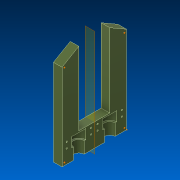
# Autodesk Inventor part: Floating Bed
Saved by Autodesk Inventor 2019 (Build 230136000, 136)
## iProperties
Created: 2019-03-21
Part Number: Floating Bed
Material: Generic
Document SubType Name: Modeling
Designer: Dell
Density: 1 g/cm^3
Appearance: Dark Olive
Mass: 1279.76 g
Surface Area: 1497.37 cm^2
Volume: 1279.76 cm^3
Author: Dell
Autodesk Inventor part; units mm, degrees
ref_plane "YZ Plane" through (0, 0, 0) normal (1, 0, 0) x (0, 1, 0)
ref_plane "XZ Plane" through (0, 0, 0) normal (0, 1, 0) x (-1, 0, 0)
ref_plane "XY Plane" through (0, 0, 0) normal (0, 0, 1) x (1, 0, 0)
sketch "Sketch1" plane through (0, 0, 0) normal (1, 0, 0) x (0, 1, 0)
  line L0 (80, 58.9167) -> (338.775, 58.9167)
  line L1 (80, 167.0833) -> (80, 58.9167)
  line L2 (336.4656, 167.0833) -> (80, 167.0833)
  line L3 (302.45, 226) -> (336.4656, 167.0833)
  line L4 (0, 226) -> (302.45, 226)
  line L5 (0, 226) -> (0, 0)
  line L6 (304.7594, 0) -> (0, 0)
  line L7 (304.7594, 0) -> (338.775, 58.9167)
  point P0 (0, 113)
  constraints: 16 end point
extrude "Extrusion1" add sketch "Sketch1" along normal blind 30
sketch "Sketch6" plane through (30, 0, 0) normal (1, 0, 0) x (0, 0, -1)
  circle A0 centre (-217.9704, 297.7535) radius 1.5 projected
  circle A1 centre (-218.1266, 9.9435) radius 1.5 projected
  circle A2 centre (-7.9983, 9.9012) radius 1.5 projected
  circle A3 centre (-7.8606, 297.8416) radius 1.5 projected
  point P0 (0, 0)
sketch "Sketch7" plane through (30, 0, 0) normal (1, 0, 0) x (0, 0, -1)
  point P0 (0, 0)
  point P1 (-7.8989, 9.8938)
  point P2 (-218.0482, 10.1478)
  point P3 (-218.2874, 297.6442)
  point P4 (-8.5245, 297.8695)
hole "Hole1" at (30, 9.8938, 7.8989) at (30, 10.1478, 218.0482) at (30, 297.6442, 218.2874) at (30, 297.8695, 8.5245) direction (-1, 0, 0) diameter 3 depth 10 tip angle 118
ref_plane "Work Plane1" through (0, 0, 113) normal (0, 0, 1) x (1, 0, 0)
sketch "Sketch12" plane through (30, 0, 0) normal (1, 0, 0) x (0, 0, -1)
  circle A0 centre (-218.2874, 297.6442) radius 1.5 projected
  circle A1 centre (-7.8989, 9.8938) radius 1.5 projected
  circle A2 centre (-218.0482, 10.1478) radius 1.5 projected
  circle A3 centre (-8.5245, 297.8695) radius 1.5 projected
  line L0 (-58.9167, 338.775) -> (-58.9167, 80) projected
  line L1 (-58.9167, 80) -> (-167.0833, 80) projected
  line L2 (-167.0833, 80) -> (-167.0833, 336.4656) projected
  line L3 (-167.0833, 336.4656) -> (-226, 302.45) projected
  line L4 (-226, 302.45) -> (-226, 0) projected
  line L5 (-226, 0) -> (0, 0) projected
  line L6 (0, 0) -> (0, 304.7594) projected
  line L7 (0, 304.7594) -> (-58.9167, 338.775) projected
  line L8 (-167.0833, 0) -> (-167.0833, 75)
  line L9 (-167.0833, 75) -> (-191.5833, 75)
  line L10 (-191.5833, 75) -> (-191.5833, 41)
  line L11 (-191.5833, 41) -> (-185.5833, 41)
  line L12 (-185.5833, 41) -> (-185.5833, 0)
  line L13 (-226, 0) -> (0, 0) projected
  line L14 (-167.0833, 0) -> (-185.5833, 0)
  dimension "d46" = 75
  dimension "d47" = 24.5
  dimension "d48" = 34
  dimension "d49" = 6
  constraints: 12 end point, 6 perpendicular, 2 point on line
  measures "d46" distance of L8.start L8.end
  measures "d47" distance of L8.end L9.end
  measures "d48" distance of L9.end L10.end
  measures "d49" distance of L10.end L11.end
revolve "Revolution1" cut sketch "Sketch12" angle 360 about axis through (30, 0, 167.0833) along (0, 1, 0) contours L5 L12 L11 L10 L9 L8
mirror "Mirror2" about plane through (0, 0, 113) normal (0, 0, 1) of "Revolution1"
sketch "Sketch13" plane through (30, 0, 0) normal (1, 0, 0) x (0, 0, -1)
  line L0 (-40.4167, 41) -> (-40.4167, 0) projected
  line L1 (-40.4167, 0) -> (0, 0) projected
  line L2 (0, 0) -> (0, 304.7594) projected
  line L3 (0, 304.7594) -> (-58.9167, 338.775) projected
  line L4 (-58.9167, 338.775) -> (-58.9167, 80) projected
  line L5 (-58.9167, 80) -> (-167.0833, 80) projected
  line L6 (-167.0833, 80) -> (-167.0833, 336.4656) projected
  line L7 (-167.0833, 336.4656) -> (-226, 302.45) projected
  line L8 (-226, 302.45) -> (-226, 0) projected
  line L9 (-226, 0) -> (-185.5833, 0) projected
  line L10 (-185.5833, 0) -> (-185.5833, 41) projected
  line L11 (-185.5833, 41) -> (-191.5833, 41) projected
  line L12 (-191.5833, 41) -> (-191.5833, 75) projected
  line L13 (-191.5833, 75) -> (-142.5833, 75) projected
  line L14 (-142.5833, 75) -> (-142.5833, 41) projected
  line L15 (-142.5833, 41) -> (-148.5833, 41) projected
  line L16 (-148.5833, 41) -> (-148.5833, 0) projected
  line L17 (-148.5833, 0) -> (-77.4167, 0) projected
  line L18 (-77.4167, 0) -> (-77.4167, 41) projected
  line L19 (-77.4167, 41) -> (-83.4167, 41) projected
  line L20 (-83.4167, 41) -> (-83.4167, 75) projected
  line L21 (-83.4167, 75) -> (-34.4167, 75) projected
  line L22 (-34.4167, 75) -> (-34.4167, 41) projected
  line L23 (-34.4167, 41) -> (-40.4167, 41) projected
  circle A0 centre (-8.5245, 297.8695) radius 1.5 projected
  circle A1 centre (-218.0482, 10.1478) radius 1.5 projected
  circle A2 centre (-7.8989, 9.8938) radius 1.5 projected
  circle A3 centre (-218.2874, 297.6442) radius 1.5 projected
  line L24 (-34.4167, 75) -> (-34.4167, 41) projected
  line L25 (-34.4167, 75) -> (-83.4167, 75) projected
  line L26 (-83.4167, 41) -> (-83.4167, 75) projected
  line L27 (-34.4167, 41) -> (-83.4167, 41) projected
  line L28 (-58.9167, 58) -> (-16.4167, 58)
  line L29 (-16.4167, 58) -> (-101.4167, 58)
  line L30 (-101.4167, 58) -> (-101.4167, 68)
  line L31 (-101.4167, 58) -> (-101.4167, 48)
  line L32 (-101.4167, 48) -> (-16.4167, 48)
  line L33 (-16.4167, 48) -> (-16.4167, 68)
  circle A4 centre (-101.4167, 68) radius 2.5
  circle A5 centre (-101.4167, 48) radius 2.5
  circle A6 centre (-16.4167, 48) radius 2.5
  circle A7 centre (-16.4167, 68) radius 2.5
  dimension "d51" = 42.5
  dimension "d52" = 85
  dimension "d56" = 10
  dimension "d57" = 10
  dimension "d58" = 5
  dimension "d59" = 5
  dimension "d60" = 5
  dimension "d61" = 5
  constraints: 12 end point, 4 centre point, 4 coincident, 2 perpendicular, 2 vertical, 1 horizontal, 1 point on line
  measures "d51" distance of L28.start L28.end
  measures "d52" distance of L28.end L29.end
  measures "d56" distance of L29.end L30.end
  measures "d57" distance of L29.end L31.end
  measures "d58" diameter of A4
  measures "d59" diameter of A5
  measures "d60" diameter of A6
  measures "d61" diameter of A7
sketch "Sketch14" plane through (30, 0, 0) normal (1, 0, 0) x (0, 0, -1)
  point P0 (0, 0)
hole "Hole4" at (30, 68, 101.4167) at (30, 48, 101.4167) at (30, 48, 16.4167) at (30, 68, 16.4167) direction (-1, 0, 0) diameter 5 end through all
mirror "Mirror3" about plane through (0, 0, 113) normal (0, 0, 1) of "Hole4"
body "Solid1"
